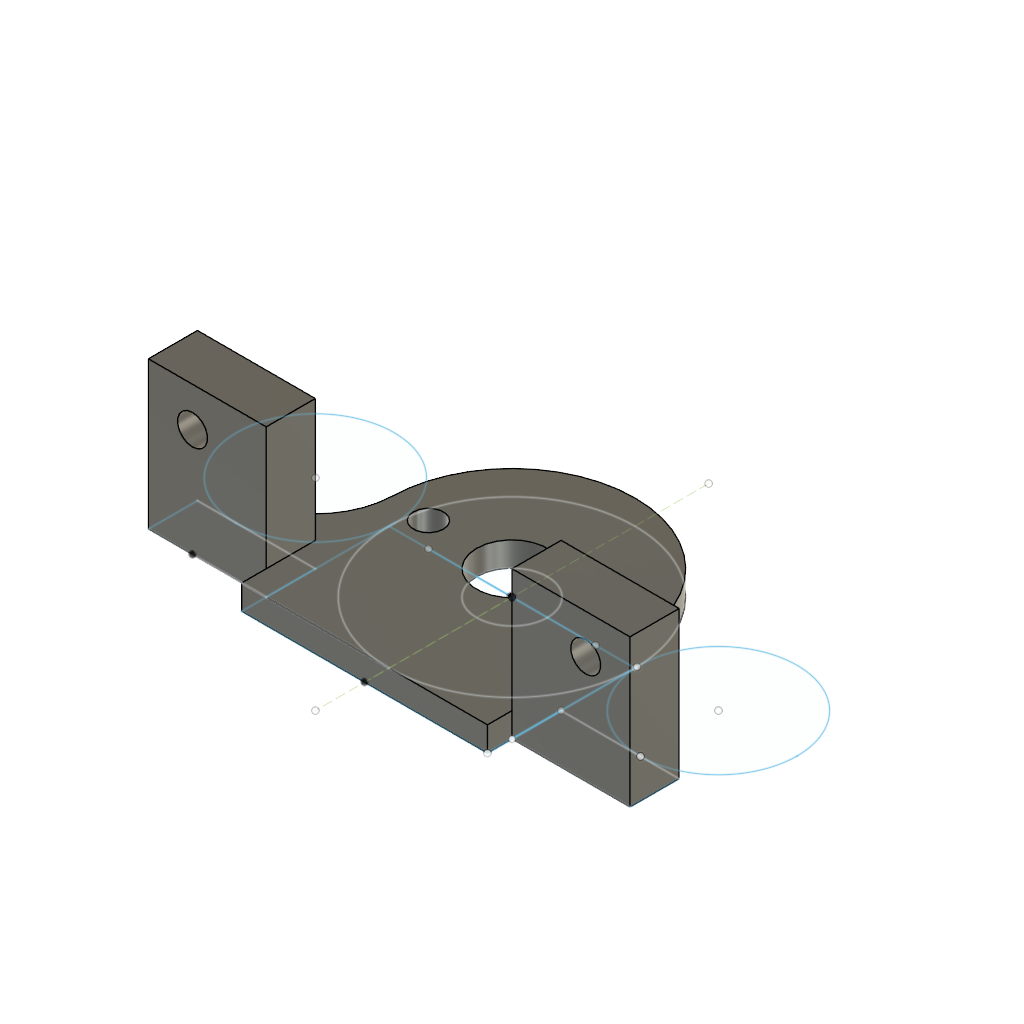
MotorStrap (Autodesk Fusion 360 design; units mm, degrees)
part number: 2026-07-06-21-27-23-966
Autodesk Fusion 360 part; units mm, degrees
sketch "Sketch1" plane through (0, 0, 0) normal (0, 0, 1) x (1, 0, 0)
  circle A0 centre (0, 0) radius 12.5
  line L0 (0, 20) -> (0, -20) construction
  line L1 (-8.5, 0) -> (8.5, 0)
  circle A1 centre (0, 0) radius 3.6
  line L2 (0, 0) -> (0, -15) construction
  line L3 (-12.5, 0) -> (12.5, 0)
  line L4 (12.5, 0) -> (12.5, -15)
  line L5 (12.5, -15) -> (-12.5, -15)
  line L6 (-12.5, -15) -> (-12.5, 0)
  line L7 (0, -12.5) -> (-20, -12.5)
  line L8 (-12.5, -12.5) -> (-24.5, -12.5)
  line L9 (-24.5, -12.5) -> (-24.5, -7.5)
  line L10 (-24.5, -7.5) -> (-12.5, -7.5)
  line L11 (-12.5, -7.5) -> (-12.5, -12.5)
  line L12 (12.5, -7.5) -> (12.5, -12.5)
  line L13 (12.5, -12.5) -> (24.5, -12.5)
  line L14 (24.5, -12.5) -> (24.5, -7.5)
  line L15 (24.5, -7.5) -> (12.5, -7.5)
  line L16 (12.5, -7.5) -> (12.5, -12.5)
  circle A2 centre (-20.5, 0.5) radius 8
  line L17 (-20.5693, -7.4997) -> (-20.5693, -7.5)
  line L18 (-12.5049, 0.2205) -> (-12.4981, 0.2196)
  circle A3 centre (20.5, 0.5) radius 8
  line L19 (12.5, -15) -> (12.5, 0)
  line L20 (12.5049, 0.2205) -> (12.4981, 0.2196)
  point P0 (20.5693, -7.5)
  point P1 (20.5693, -7.4997)
  dimension "d1" = 25
  dimension "d2" = 17
  dimension "d3" = 7.2
  dimension "d4" = 15
  dimension "d5" = 25
  dimension "d6" = 15
  dimension "d11" = 20
  dimension "d12" = 12
  dimension "d13" = 5
  dimension "d19" = 8
  constraint coincident A0.centre A1.centre
  constraint vertical L0
  constraint horizontal L1
  constraint symmetric L0 L1.start L1.end
  constraint concentric A0 A1
  constraint parallel L0 L2
  constraint horizontal L3
  constraint vertical L4
  constraint horizontal L5
  constraint vertical L6
  constraint coincident A0 L3.start
  constraint coincident A0 L7.start
  constraint coincident L0 L7.start
  constraint perpendicular L6 L7
  constraint horizontal L8
  constraint vertical L9
  constraint horizontal L10
  constraint vertical L11
  constraint coincident L6 L8.start
  constraint coincident L7 L8.start
  constraint symmetric L2 L8.start L12.end
  constraint symmetric L2 L10.end L12.start
  constraint symmetric L2 L8.end L13.end
  constraint symmetric L2 L9.end L14.end
  constraint tangent L6 A2
  constraint tangent L10 A2
  constraint coincident A2 L17.start
  constraint coincident L10 L17.end
  constraint perpendicular L10 L17
  constraint coincident A2 L18.start
  constraint coincident A0 L18.end
  constraint symmetric L0 L3.start L3.end
  constraint symmetric L0 L5.end L4.end
  constraint symmetric L0 A2 A3
  constraint symmetric L0 L17.start P1
  constraint symmetric L0 L17.end P0
  constraint symmetric L0 L18.start L20.start
  constraint symmetric L0 L18.end L20.end
  measures "d1" diameter of A0
  measures "d2" distance of L1.start L1.end
  measures "d3" diameter of A1
  measures "d4" distance of A0.centre L2.end
  measures "d5" distance of L3.start L3.end
  measures "d6" distance of L3.start L5.end
  measures "d11" distance of L7.start L7.end
  measures "d12" distance of L8.start L8.end
  measures "d13" distance of L8.start L10.end
  measures "d19" radius of A2
extrude "Extrude1" add sketch "Sketch1" along normal blind 2.5 contours A0 L1 A1 L3 | A0 L4 L5 L6 L7 L12 L16 L19 | A0 L1 A1 L3 | A0 L4 L15 A3 L19 L20 | A0 L6 L7 L11 | A0 L6 L10 A2 L18
hole "Hole1" at (8.5, 0, 0) at (-8.5, 0, 0) direction (0, 0, 1) diameter 3.05 end through all
extrude "Extrude2" add sketch "Sketch1" along normal blind 15 contours L4 L12 L13 L14 L15 L16 L19 | L6 L7 L8 L9 L10 L11
sketch "Sketch2" plane through (0, -7.5, 0) normal (0, 1, 0) x (-1, 0, 0)
  line L0 (-24.5, 0) -> (-20.5, 0)
  line L1 (-12.5, 2.5) -> (-12.5, 15)
  line L2 (-12.5, 15) -> (-24.5, 15)
  line L3 (-24.5, 15) -> (-24.5, 0)
  line L4 (-20.5, 0) -> (-28, 0)
  line L5 (-28, 0) -> (-28, 11)
  line L6 (0, -12) -> (0, 18)
  line L7 (-20.5, 0) -> (-20.5, 2.5)
  line L8 (-20.5, 2.5) -> (-12.5, 2.5)
  line L9 (-28, 11) -> (-20, 11)
  line L10 (28, 11) -> (20, 11)
  point P0 (28, 11)
  dimension "d16" = 7.5
  dimension "d17" = 11
  dimension "d18" = 30
  dimension "d20" = 8
  constraint coincident L0.end L4.start
  constraint coincident L0 L4.end
  constraint perpendicular L4 L5
  constraint vertical L6
  constraint symmetric L5.end L6 P0
  constraint perpendicular L5 L9
  constraint coincident P0 L10.start
  constraint horizontal L10
  measures "d16" distance of L0.end L4.end
  measures "d17" distance of L4.end L5.end
  measures "d18" distance of L6.start L6.end
  measures "d20" distance of L5.end L9.end
hole "Hole2" at (20, -7.5, 11) at (-20, -7.5, 11) direction (0, -1, 0) diameter 3.05 end through all
equation "d4 = 12.500 mm + 2.5 mm"
equation "d11 = 12.5 mm + 7.5 mm"
